TOPDON_TC001_Max (Autodesk Fusion 360 design; units mm, degrees)
part number: 2026-11-21-15-15-09-937
Autodesk Fusion 360 part; units mm, degrees
sketch "S_FrontSilhouette" plane through (0, 0, 0) normal (0, 0, 1) x (1, 0, 0)
  line L0 (-29.5, 0) -> (29.5, 0)
  line L1 (29.5, 0) -> (35.5, -6)
  line L2 (35.5, -6) -> (35.5, -28.7)
  line L3 (35.5, -28.7) -> (33, -31.2)
  line L4 (33, -31.2) -> (-33, -31.2)
  line L5 (-33, -31.2) -> (-35.5, -28.7)
  line L6 (-35.5, -28.7) -> (-35.5, -6)
  line L7 (-35.5, -6) -> (-29.5, 0)
  point P0 (-100, 100)
  dimension "d135" = 70.5
  dimension "d136" = 100
  dimension "d137" = 129.5
  dimension "d138" = 135.5
  dimension "d139" = 106
  dimension "d140" = 128.7
  dimension "d141" = 133
  dimension "d142" = 131.2
  dimension "d143" = 67
  dimension "d144" = 64.5
  dimension "d145" = 128.7
  dimension "d146" = 106
  constraint horizontal L0
  constraint vertical L2
  constraint horizontal L4
  constraint vertical L6
  measures "d135" horizontal distance of P0 L0.start
  measures "d136" vertical distance of P0 L0.start
  measures "d137" horizontal distance of P0 L0.end
  measures "d138" horizontal distance of P0 L1.end
  measures "d139" vertical distance of P0 L1.end
  measures "d140" vertical distance of P0 L2.end
  measures "d141" horizontal distance of P0 L3.end
  measures "d142" vertical distance of P0 L3.end
  measures "d143" horizontal distance of P0 L4.end
  measures "d144" horizontal distance of P0 L5.end
  measures "d145" vertical distance of P0 L5.end
  measures "d146" vertical distance of P0 L6.end
extrude "Body" add sketch "S_FrontSilhouette" against normal blind 14 makes body 1
chamfer "FrontTopBevel" distance 3 distance2 5.6 1 edges at (0, 0, 0) measured on face at (-9.8333, 0, -4.6667) tangent chain off on bodies 1
fillet "BottomEdgeRounds" radius 1 2 edges at (0, -31.2, 0) (0, -31.2, -14) on bodies 1
sketch "S_LensWindow" plane through (0, 0, 0) normal (0, 0, 1) x (1, 0, 0)
  line L0 (-30.2, -29.6) -> (-10.2, -29.6)
  line L1 (-10.2, -29.6) -> (-0.35, -6)
  line L2 (-0.35, -6) -> (-20.35, -6)
  line L3 (-20.35, -6) -> (-30.2, -29.6)
  point P0 (-100, 100)
  dimension "d155" = 69.8
  dimension "d156" = 129.6
  dimension "d157" = 89.8
  dimension "d158" = 99.65
  dimension "d159" = 106
  dimension "d160" = 79.65
  constraint horizontal L0
  constraint horizontal L2
  measures "d155" horizontal distance of P0 L0.start
  measures "d156" vertical distance of P0 L0.start
  measures "d157" horizontal distance of P0 L0.end
  measures "d158" horizontal distance of P0 L1.end
  measures "d159" vertical distance of P0 L1.end
  measures "d160" horizontal distance of P0 L2.end
extrude "LensWindowRecess" cut sketch "S_LensWindow" against normal blind 0.3 bodies 1
sketch "S_Lenses" plane through (0, 0, 0) normal (0, 0, 1) x (1, 0, 0)
  circle A0 centre (-15.6, -12.3) radius 4.95
  circle A1 centre (-15.8, -24.1) radius 5.3
  point P0 (-100, 100)
  dimension "d163" = 84.4
  dimension "d164" = 112.3
  dimension "d165" = 9.9
  dimension "d166" = 84.2
  dimension "d167" = 124.1
  dimension "d168" = 10.6
  measures "d163" horizontal distance of P0 A0.centre
  measures "d164" vertical distance of P0 A0.centre
  measures "d165" diameter of A0
  measures "d166" horizontal distance of P0 A1.centre
  measures "d167" vertical distance of P0 A1.centre
  measures "d168" diameter of A1
extrude "LensRings" cut sketch "S_Lenses" against normal blind 1.3 bodies 1
ref_plane "WorkPlane12" through (35.5, 0, 0) normal (1, 0, 0) x (0, 1, 0)
sketch "S_Pinhole" plane through (35.5, 0, 0) normal (1, 0, 0) x (0, 0, -1)
  circle A0 centre (4, -15.6) radius 0.4
  point P0 (-100, 100)
  dimension "d173" = 104
  dimension "d174" = 115.6
  dimension "d175" = 0.8
  measures "d173" horizontal distance of P0 A0.centre
  measures "d174" vertical distance of P0 A0.centre
  measures "d175" diameter of A0
extrude "Pinhole" cut sketch "S_Pinhole" against normal blind 1 bodies 1
ref_plane "WorkPlane13" through (33.5, 0, 0) normal (1, 0, 0) x (0, 1, 0)
ref_plane "WorkPlane14" through (-33.5, 0, 0) normal (1, 0, 0) x (0, 1, 0)
split "SplitCapPlusX" by plane through (33.5, 0, 0) normal (1, 0, 0) bodies 1 makes body 2 at (35.5, -16.7865, -10.7985)
split "SplitCapMinusX" by plane through (-33.5, 0, 0) normal (1, 0, 0) bodies 1 2 makes body 3 at (9.8333, -20.1333, -14)
sketch "S_USB_Collar" plane through (0, 0, 0) normal (0, 1, 0) x (1, 0, 0)
  line L0 (-5.2, 9) -> (5.2, 9)
  line L1 (5.2, 9) -> (5.2, 5)
  line L2 (5.2, 5) -> (-5.2, 5)
  line L3 (-5.2, 5) -> (-5.2, 9)
  point P0 (-100, 100)
  dimension "d182" = 91
  dimension "d183" = 105.2
  dimension "d184" = 95
  dimension "d185" = 94.8
  constraint horizontal L0
  constraint vertical L1
  constraint horizontal L2
  constraint vertical L3
  measures "d182" vertical distance of P0 L0.start
  measures "d183" horizontal distance of P0 L0.end
  measures "d184" vertical distance of P0 L1.end
  measures "d185" horizontal distance of P0 L2.end
extrude "USB_Collar" add sketch "S_USB_Collar" along normal blind 1 separate body makes body 4
ref_plane "WorkPlane15" through (0, 1, 0) normal (0, 1, 0) x (0, 0, 1)
sketch "S_USB_Plug" plane through (0, 1, 0) normal (0, 1, 0) x (1, 0, 0)
  line L0 (-4.125, 8.2) -> (4.125, 8.2)
  line L1 (4.125, 8.2) -> (4.125, 5.8)
  line L2 (4.125, 5.8) -> (-4.125, 5.8)
  line L3 (-4.125, 5.8) -> (-4.125, 8.2)
  point P0 (-100, 100)
  dimension "d190" = 91.8
  dimension "d191" = 104.125
  dimension "d192" = 94.2
  dimension "d193" = 95.875
  constraint horizontal L0
  constraint vertical L1
  constraint horizontal L2
  constraint vertical L3
  measures "d190" vertical distance of P0 L0.start
  measures "d191" horizontal distance of P0 L0.end
  measures "d192" vertical distance of P0 L1.end
  measures "d193" horizontal distance of P0 L2.end
extrude "USB_C_Plug" add sketch "S_USB_Plug" along normal blind 7.7 separate body makes body 5
fillet "USB_C_PlugEnds" radius 1.15 4 edges at (-4.125, 4.85, -5.8) (-4.125, 4.85, -8.2) (4.125, 4.85, -8.2) (4.125, 4.85, -5.8) on bodies 5
sketch "S_PlugEnvelope" plane through (0, 0, 0) normal (0, 1, 0) x (1, 0, 0)
  line L0 (-5.7, 9.5) -> (5.7, 9.5)
  line L1 (5.7, 9.5) -> (5.7, 4.5)
  line L2 (5.7, 4.5) -> (-5.7, 4.5)
  line L3 (-5.7, 4.5) -> (-5.7, 9.5)
  point P0 (-100, 100)
  dimension "d198" = 90.5
  dimension "d199" = 105.7
  dimension "d200" = 95.5
  dimension "d201" = 94.3
  constraint horizontal L0
  constraint vertical L1
  constraint horizontal L2
  constraint vertical L3
  measures "d198" vertical distance of P0 L0.start
  measures "d199" horizontal distance of P0 L0.end
  measures "d200" vertical distance of P0 L1.end
  measures "d201" horizontal distance of P0 L2.end
extrude "PlugEnvelope" add sketch "S_PlugEnvelope" along normal blind 9.2 separate body makes body 6
ref_plane "WorkPlane16" through (0, 0, 0) normal (0, 0, 1) x (1, 0, 0)
ref_plane "WorkPlane17" through (0, 0, -14) normal (0, 0, 1) x (1, 0, 0)
ref_plane "WorkPlane18" through (0, -31.2, 0) normal (0, 1, 0) x (0, 0, 1)
ref_plane "WorkPlane19" through (0, 0, 0) normal (0, 1, 0) x (0, 0, 1)
ref_plane "WorkPlane20" through (0, 8.7, 0) normal (0, 1, 0) x (0, 0, 1)
ref_plane "WorkPlane21" through (0, 0, 0) normal (1, 0, 0) x (0, 1, 0)
ref_plane "WorkPlane22" through (0, 0, -7) normal (0, 0, 1) x (1, 0, 0)
equation "body_L = 71 mm" comment "Body length X. Listing 7.1 cm / 2.8 in. CONFIRMED-ish"
equation "body_H = 31.2 mm" comment "Body height, plug face to opposite face, plug excluded. ESTIMATE photo-scaled; listing says 42 incl plug? MEASURE FIRST"
equation "body_T = 14 mm" comment "Body thickness Z, lens face to back face. Listing 0.55 in. MEASURE"
equation "endcap_W = 2 mm" comment "Black end cap thickness along X. ESTIMATE"
equation "chamfer_top = 6 mm" comment "Front-view chamfer at the two plug-side corners. ESTIMATE"
equation "chamfer_bot = 2.5 mm" comment "Front-view chamfer at the two bottom corners. ESTIMATE"
equation "bevel_front = 5.6 mm" comment "Front-top long-edge bevel: height on front face. ESTIMATE"
equation "bevel_top = 3 mm" comment "Front-top long-edge bevel: depth into top face. ESTIMATE weak"
equation "edge_R = 1 mm" comment "Round on the two bottom long edges. ESTIMATE"
equation "win_top = 6 mm" comment "Lens window top edge below top face. ESTIMATE"
equation "win_H = 23.6 mm" comment "Lens window height. ESTIMATE"
equation "win_W = 20 mm" comment "Lens window width along X. ESTIMATE"
equation "win_X0 = 5.3 mm" comment "Lens window bottom-left corner from -X end. ESTIMATE"
equation "win_shear = 9.85 mm" comment "Lens window slant: top edge shifted toward +X. ESTIMATE"
equation "win_depth = 0.3 mm" comment "Lens window recess depth. ESTIMATE"
equation "vis_X = 19.9 mm" comment "Upper (visible?) lens centre from -X end. ESTIMATE"
equation "vis_Y = 12.3 mm" comment "Upper (visible?) lens centre below top face. ESTIMATE"
equation "vis_D = 9.9 mm" comment "Upper lens ring diameter. ESTIMATE"
equation "ir_X = 19.7 mm" comment "Lower (thermal?) lens centre from -X end. ESTIMATE"
equation "ir_Y = 24.1 mm" comment "Lower (thermal?) lens centre below top face. ESTIMATE"
equation "ir_D = 10.6 mm" comment "Lower lens ring diameter. ESTIMATE"
equation "lens_recess = 1 mm" comment "Lens ring recess below window. ESTIMATE"
equation "pin_D = 0.8 mm" comment "Pinhole on +X end cap, diameter. ESTIMATE"
equation "pin_Y = body_H / 2" comment "Pinhole centre below top face. ESTIMATE"
equation "pin_Z = 4 mm" comment "Pinhole centre behind front face. ESTIMATE"
equation "plug_X = 0 mm" comment "USB-C plug centre offset along X from body centre (+ = away from lenses). ESTIMATE"
equation "plug_Z = body_T / 2" comment "USB-C plug centre distance behind front (lens) face. ESTIMATE weak"
equation "usbc_W = 8.25 mm" comment "USB-C plug shell width. USB Type-C spec"
equation "usbc_T = 2.4 mm" comment "USB-C plug shell thickness. USB Type-C spec"
equation "usbc_R = 1.15 mm" comment "USB-C plug shell end radius (just under usbc_T/2)"
equation "usbc_L = 7.7 mm" comment "USB-C plug exposed length, collar face to tip. ESTIMATE; spec min mating 6.65"
equation "collar_W = 10.4 mm" comment "Black collar under plug, X width. ESTIMATE"
equation "collar_D = 4 mm" comment "Black collar under plug, Z depth. ESTIMATE guess"
equation "collar_H = 1 mm" comment "Black collar height above top face (= receptacle seat). ESTIMATE"
equation "env_clr = 0.5 mm" comment "Clearance added around collar+plug for PlugEnvelope keep-out"
equation "sk_ref = 100 mm" comment "Sketch datum offset used by dimension expressions. Do not edit"
equation "d135 = sk_ref + ( ( -body_L / 2 + chamfer_top ) )"
equation "d136 = sk_ref - ( ( 0 mm ) )"
equation "d137 = sk_ref + ( ( body_L / 2 - chamfer_top ) )"
equation "d138 = sk_ref + ( ( body_L / 2 ) )"
equation "d139 = sk_ref - ( ( -chamfer_top ) )"
equation "d140 = sk_ref - ( ( -body_H + chamfer_bot ) )"
equation "d141 = sk_ref + ( ( body_L / 2 - chamfer_bot ) )"
equation "d142 = sk_ref - ( ( -body_H ) )"
equation "d143 = sk_ref + ( ( -body_L / 2 + chamfer_bot ) )"
equation "d144 = sk_ref + ( ( -body_L / 2 ) )"
equation "d145 = sk_ref - ( ( -body_H + chamfer_bot ) )"
equation "d146 = sk_ref - ( ( -chamfer_top ) )"
equation "d147 = -( body_T )"
equation "d151 = bevel_top"
equation "d152 = bevel_front"
equation "d154 = edge_R"
equation "d155 = sk_ref + ( ( -body_L / 2 + win_X0 ) )"
equation "d156 = sk_ref - ( ( -( win_top + win_H ) ) )"
equation "d157 = sk_ref + ( ( -body_L / 2 + win_X0 + win_W ) )"
equation "d158 = sk_ref + ( ( -body_L / 2 + win_X0 + win_W + win_shear ) )"
equation "d159 = sk_ref - ( ( -win_top ) )"
equation "d160 = sk_ref + ( ( -body_L / 2 + win_X0 + win_shear ) )"
equation "d161 = -( win_depth )"
equation "d163 = sk_ref + ( ( -body_L / 2 + vis_X ) )"
equation "d164 = sk_ref - ( ( -vis_Y ) )"
equation "d165 = vis_D"
equation "d166 = sk_ref + ( ( -body_L / 2 + ir_X ) )"
equation "d167 = sk_ref - ( ( -ir_Y ) )"
equation "d168 = ir_D"
equation "d169 = -( win_depth + lens_recess )"
equation "d171 = body_L / 2"
equation "d173 = sk_ref + ( -( -pin_Z ) )"
equation "d174 = sk_ref - ( ( -pin_Y ) )"
equation "d175 = pin_D"
equation "d176 = -( 1 mm )"
equation "d178 = body_L / 2 - endcap_W"
equation "d180 = -( body_L / 2 - endcap_W )"
equation "d182 = sk_ref - ( -( -plug_Z - collar_D / 2 ) )"
equation "d183 = sk_ref + ( ( plug_X + collar_W / 2 ) )"
equation "d184 = sk_ref - ( -( -plug_Z + collar_D / 2 ) )"
equation "d185 = sk_ref + ( ( plug_X - collar_W / 2 ) )"
equation "d186 = collar_H"
equation "d188 = collar_H"
equation "d190 = sk_ref - ( -( -plug_Z - usbc_T / 2 ) )"
equation "d191 = sk_ref + ( ( plug_X + usbc_W / 2 ) )"
equation "d192 = sk_ref - ( -( -plug_Z + usbc_T / 2 ) )"
equation "d193 = sk_ref + ( ( plug_X - usbc_W / 2 ) )"
equation "d194 = usbc_L"
equation "d197 = usbc_R"
equation "d198 = sk_ref - ( -( -plug_Z - collar_D / 2 - env_clr ) )"
equation "d199 = sk_ref + ( ( plug_X + collar_W / 2 + env_clr ) )"
equation "d200 = sk_ref - ( -( -plug_Z + collar_D / 2 + env_clr ) )"
equation "d201 = sk_ref + ( ( plug_X - collar_W / 2 - env_clr ) )"
equation "d202 = collar_H + usbc_L + env_clr"
equation "d206 = -body_T"
equation "d208 = -body_H"
equation "d212 = collar_H + usbc_L"
equation "d214 = plug_X"
equation "d216 = -plug_Z"
named bodies: "EndCap_MinusX", "EndCap_PlusX", "Shell", "USB_Collar", "USB_C_Plug", "PlugEnvelope"
